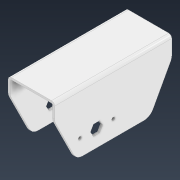
# Autodesk Inventor part: SP23V1 Pedal Izquierdo
Saved by Autodesk Inventor 2021.2 (Build 252289000, 289)
## iProperties
Created: 2026-06-16
Part Number: SP23V1 Pedal Izquierdo
Material: Steel, Carbon
Document SubType Name: Sheet Metal
Designer: nelso
Density: 7.87 g/cm^3
Sheet Metal Rule: Default_mm
Appearance: White
Mass: 129.606 g
Surface Area: 863.649 cm^2
Volume: 129.606 cm^3
Flat Pattern Width: 17.5 cm
Flat Pattern Length: 23.7633 cm
Flat Pattern Area: 415.858 cm^2
Sheet Metal Width: 175.000 mm
Sheet Metal Length: 237.633 mm
Sheet Metal Area: 41585.751 mm^2
Author: nelso
Autodesk Inventor part; units mm, degrees
ref_plane "YZ Plane" through (0, 0, 0) normal (1, 0, 0) x (0, 1, 0)
ref_plane "XZ Plane" through (0, 0, 0) normal (0, 1, 0) x (-1, 0, 0)
ref_plane "XY Plane" through (0, 0, 0) normal (0, 0, 1) x (1, 0, 0)
sketch "Sketch1" plane through (0, 0, 0) normal (0, 1, 0) x (-1, 0, 0)
  line L0 (-30, -87.5) -> (30, -87.5)
  line L1 (30, -87.5) -> (30, 87.5)
  line L2 (30, 87.5) -> (-30, 87.5)
  line L3 (-30, 87.5) -> (-30, -87.5)
  line L4 (-30, -87.5) -> (30, 87.5) construction
  line L5 (30, -87.5) -> (-30, 87.5) construction
  line L6 (30, 0) -> (30, 40)
  line L7 (30, 0) -> (30, -25)
  line L8 (-30, -87.5) -> (0, -87.5)
  line L9 (-30, -87.5) -> (30, -87.5)
  line L10 (30, -25) -> (30, -87.5)
  line L11 (30, 40) -> (40, 87.5)
  point P0 (0, 0)
  dimension "d0" = 60
  dimension "d1" = 175
  dimension "d2" = 40
  dimension "d3" = 25
  dimension "d5" = 60
  dimension "d6" = 70
  measures "d0" distance of L2.end L1.end
  measures "d1" distance of L1.end L0.end
  measures "d2" distance of L6.start L6.end
  measures "d3" distance of L6.start L7.end
  measures "d5" distance of L9.end L0.start
  measures "d6" distance of L11.end L2.end
extrude "Plate1" add sketch "Sketch1" along normal blind 3.2
sketch "Sketch2" plane through (31.516, -1.516, 87.5) normal (1, 0, 0) x (0, 1, 0)
  line L0 (0, -175) -> (0, 0)
  line L1 (0, 0) -> (-85.284, 0)
  line L2 (-85.284, 0) -> (-85.284, -175)
  line L3 (-85.284, -175) -> (0, -175)
  constraints: 6 end point, 1 horizontal, 1 perpendicular, 1 vertical
edge flange "Flange1" height 90 angle 90 thickness 3.2 bend radius 1.516 thickness toward (1, 0, 0) relief straight relief width 3.2 relief depth 1.6 corner gap 1.516 corner form 0 edges at (30, 0, 0) (-30, 0, 63.75) (-30, 0, 20) (-30, 0, -12.5) (-30, 0, -56.25) wall of the first edge with corners at (31.516, -1.516, -87.5) (31.516, -1.516, 87.5) (31.516, -86.8, 87.5) (31.516, -86.8, -87.5)
bend "Bend1"
corner "Corner1"
sketch "Sketch5" plane through (34.716, -86.8, 87.5) normal (1, 0, 0) x (0, 0, -1)
  line L0 (0, 90) -> (175, 90) projected
  line L1 (0, 90) -> (0, 65)
  line L2 (0, 0) -> (0, 85.284) projected
  line L3 (175, 0) -> (0, 0) projected
  line L4 (87.5, 0) -> (142.5, 0)
  line L5 (142.5, 0) -> (175, 60)
  line L6 (175, 0) -> (175, 85.284) projected
  line L7 (0, 65) -> (32.5, 0)
  line L8 (32.5, 0) -> (87.5, 0)
  line L9 (0, 0) -> (175, 0) projected
  line L10 (67.1188, 17) -> (57.8812, 17)
  line L11 (57.8812, 17) -> (53.2624, 25)
  line L12 (53.2624, 25) -> (57.8812, 33)
  line L13 (57.8812, 33) -> (67.1188, 33)
  line L14 (67.1188, 33) -> (71.7376, 25)
  line L15 (71.7376, 25) -> (67.1188, 17)
  line L16 (62.5, 25) -> (37.5, 25)
  line L17 (62.5, 25) -> (62.5, 26.5786)
  line L18 (175, 0) -> (0, 0) projected
  point P0 (87.5, 86.8)
  point P1 (87.5, 25)
  dimension "d38" = 25
  dimension "d40" = 55
  dimension "d42" = 65
  dimension "d43" = 30
  dimension "d44" = 112.5
  dimension "d45" = 55
  dimension "d59" = 16
  dimension "d60" = 25
  constraints: 26 end point, 4 point on line, 2 coincident, 1 collinear, 1 horizontal, 1 midpoint, 1 parallel, 1 symmetric about line, 1 vertical, 13 other
  measures "d38" distance of L0.start L1.end
  measures "d40" distance of L4.start L4.end
  measures "d42" distance from line of L0 point (62.5, 25)
  measures "d43" distance of L0.end L5.end
  measures "d44" distance from line of L6 point (62.5, 25)
  measures "d45" distance of L4.start L7.end
  measures "d59" distance between parallel lines of L12 L15
  measures "d60" distance of L16.start L16.end
extrude "Cut3" cut sketch "Sketch5" against normal through all
hole "Hole2" at (34.716, -61.8, 50) at (34.716, -61.8, 0) direction (-1, 0, 0) diameter 4.5 depth 3.2 clearance for "Countersunk Flat Head Screw ISO 2009/7046" size "M4" standard "ISO"
fillet "Corner Round2" radius 15 8 edges at (33.116, -26.8, -87.5) (-33.116, -26.8, -87.5) (33.116, -86.8, -55) (-33.116, -86.8, -55) (-33.116, -86.8, 55) (-33.116, -21.8, 87.5) (33.116, -21.8, 87.5) (33.116, -86.8, 55)
ref_plane "Work Plane2" through (-33.116, -1.516, 87.5) normal (1, 0, 0) x (0, 0, -1)
equation "\"d36\" = Thickness"
equation "\"d66\" = Thickness"
equation "\"d7\" = Thickness"
equation "\"d8\" = BendReliefWidth"
equation "\"d9\" = BendReliefDepth"
equation "\"d10\" = MinimumRemnant"
equation "\"d11\" = TransitionRadius"
equation "\"d14\" = BendRadius"
equation "\"d15\" = CornerReliefSize"
equation "\"d16\" = GapSize"
equation "\"d17\" = JacobiRadiusSize"
equation "\"BendReliefWidth\" = Thickness"
equation "\"BendReliefDepth\" = 0.5 * Thickness"
equation "\"CornerReliefSize\" = 4 * Thickness"
equation "\"MinimumRemnant\" = 2 * Thickness"
equation "\"TransitionRadius\" = BendRadius"
equation "\"JacobiRadiusSize\" = BendRadius"
equation "\"GapSize\" = Thickness"
equation "\"Thickness\" = 3.2"
equation "\"BendRadius\" = 1.516"
body "Solid1"
